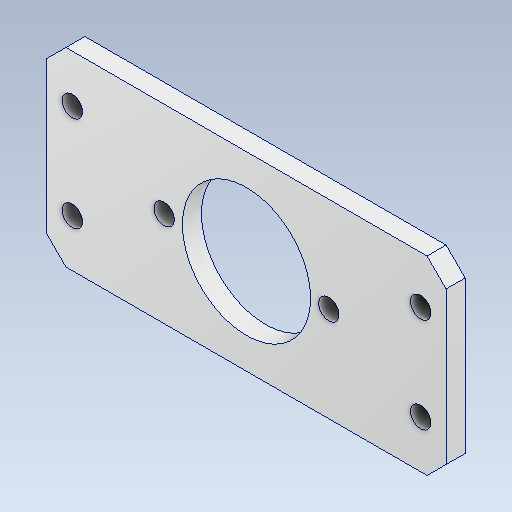
# Autodesk Inventor part: alfs_3_63_30_1
Saved by Autodesk Inventor 2027.1 (Build 311270010, 270A)
## iProperties
Created: 2026-10-20
Part Number: alfs_3_63_30_1
Material: アルミニウム 6061
Document SubType Name: Modeling
Designer: ug_nd
Density: 2.7 g/cm^3
Appearance: アルミニウム - フラット
Author: ug_nd
Autodesk Inventor part; units mm, degrees
ref_plane "YZ Plane" through (0, 0, 0) normal (1, 0, 0) x (0, 1, 0)
ref_plane "XZ Plane" through (0, 0, 0) normal (0, 1, 0) x (-1, 0, 0)
ref_plane "XY Plane" through (0, 0, 0) normal (0, 0, 1) x (1, 0, 0)
sketch "スケッチ1" plane through (0, 0, 0) normal (0, 0, 1) x (1, 0, 0)
  line L0 (-31.5, -15) -> (31.5, -15)
  line L1 (31.5, -15) -> (31.5, 15)
  line L2 (31.5, 15) -> (-31.5, 15)
  line L3 (-31.5, 15) -> (-31.5, -15)
  line L4 (-31.5, -15) -> (31.5, 15) construction
  line L5 (31.5, -15) -> (-31.5, 15) construction
  circle A0 centre (0, 0) radius 10.1
  line L6 (-44.1, 0) -> (44.1, 0) construction
  line L7 (0, -21) -> (0, 21) construction
  circle A1 centre (-27.5, 7.5) radius 1.6
  circle A2 centre (-27.5, -7.5) radius 1.6
  circle A3 centre (27.5, 7.5) radius 1.6
  circle A4 centre (27.5, -7.5) radius 1.6
  circle A5 centre (-13, 0) radius 1.6
  circle A6 centre (13, 0) radius 1.6
  point P0 (0, 0)
  dimension "d0" = 30
  dimension "d1" = 63
  dimension "d2" = 20.2
  dimension "d3" = 15
  dimension "d4" = 55
  dimension "d5" = 3.2
  dimension "d11" = 26
  dimension "d12" = 3.2
  constraints: 12 end point, 7 centre point, 4 symmetric about line, 2 midpoint, 2 parallel, 1 coincident, 1 horizontal, 1 perpendicular, 1 point on line, 4 other
  measures "d0" distance of L2.end L0.start
  measures "d1" distance of L1.end L2.end
  measures "d2" diameter of A0
  measures "d3" distance of A4.centre A3.centre
  measures "d4" distance of A4.centre A2.centre
  measures "d5" diameter of A1
  measures "d11" distance of A6.centre A5.centre
  measures "d12" diameter of A5
extrude "押し出し1" add sketch "スケッチ1" along normal mid plane 3
chamfer "面取り1" distance 3 angle 45 4 edges at (-31.5, 15, 0) (31.5, 15, 0) (31.5, -15, 0) (-31.5, -15, 0)
